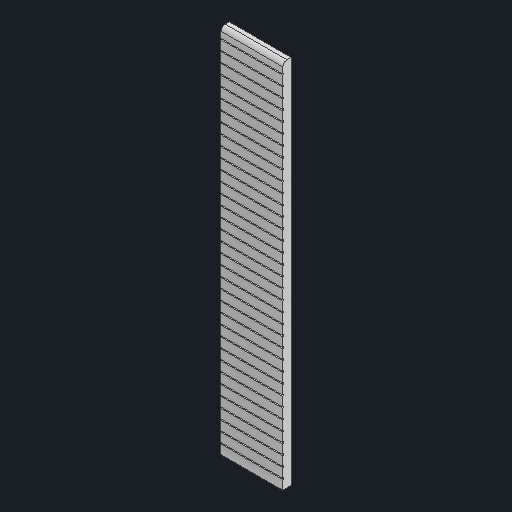
# Autodesk Inventor part: 7_1_2_1_vollet_cote_avant
Saved by Autodesk Inventor 2026 (Build 300175000, 175)
## iProperties
Created: 2025-06-21
Part Number: 7_1_2_1_vollet_cote_avant
Material: Generic
Document SubType Name: Modeling
Designer: remg9
Density: 1 g/cm^3
Appearance: Default
Author: remg9
Autodesk Inventor part; units mm, degrees
ref_plane "YZ Plane" through (0, 0, 0) normal (1, 0, 0) x (0, 1, 0)
ref_plane "XZ Plane" through (0, 0, 0) normal (0, 1, 0) x (-1, 0, 0)
ref_plane "XY Plane" through (0, 0, 0) normal (0, 0, 1) x (1, 0, 0)
sketch "Sketch1" plane through (0, 0, 0) normal (0, 0, 1) x (1, 0, 0)
  line L0 (0, 0) -> (30, 0)
  line L1 (30, 0) -> (30, 180)
  line L2 (30, 180) -> (0, 180)
  line L3 (0, 180) -> (0, 0)
  dimension "d0" = 180
  dimension "d1" = 30
  constraints: 8 end point, 2 parallel, 1 horizontal, 1 perpendicular
  measures "d0" distance of L0.end L1.end
  measures "d1" distance of L1.end L2.end
extrude "Extrusion1" add sketch "Sketch1" along normal blind 4
sketch "Sketch2" plane through (0, 0, 4) normal (0, 0, 1) x (1, 0, 0)
  line L0 (0, 175) -> (30, 175)
  line L1 (30, 175) -> (30, 174.5)
  line L2 (30, 174.5) -> (0, 174.5)
  line L3 (0, 174.5) -> (0, 175)
  line L4 (30, 0) -> (30, 180) projected
  line L5 (0, 180) -> (0, 0) projected
  line L6 (0, 170) -> (30, 170)
  line L7 (30, 170) -> (30, 169.5)
  line L8 (30, 169.5) -> (0, 169.5)
  line L9 (0, 169.5) -> (0, 170)
  line L10 (0, 165) -> (30, 165)
  line L11 (30, 165) -> (30, 164.5)
  line L12 (30, 164.5) -> (0, 164.5)
  line L13 (0, 164.5) -> (0, 165)
  line L14 (0, 160) -> (30, 160)
  line L15 (30, 160) -> (30, 159.5)
  line L16 (30, 159.5) -> (0, 159.5)
  line L17 (0, 159.5) -> (0, 160)
  line L18 (0, 155) -> (30, 155)
  line L19 (30, 155) -> (30, 154.5)
  line L20 (30, 154.5) -> (0, 154.5)
  line L21 (0, 154.5) -> (0, 155)
  line L22 (0, 150) -> (30, 150)
  line L23 (30, 150) -> (30, 149.5)
  line L24 (30, 149.5) -> (0, 149.5)
  line L25 (0, 149.5) -> (0, 150)
  line L26 (0, 145) -> (30, 145)
  line L27 (30, 145) -> (30, 144.5)
  line L28 (30, 144.5) -> (0, 144.5)
  line L29 (0, 144.5) -> (0, 145)
  line L30 (0, 140) -> (30, 140)
  line L31 (30, 140) -> (30, 139.5)
  line L32 (30, 139.5) -> (0, 139.5)
  line L33 (0, 139.5) -> (0, 140)
  line L34 (0, 135) -> (30, 135)
  line L35 (30, 135) -> (30, 134.5)
  line L36 (30, 134.5) -> (0, 134.5)
  line L37 (0, 134.5) -> (0, 135)
  line L38 (0, 130) -> (30, 130)
  line L39 (30, 130) -> (30, 129.5)
  line L40 (30, 129.5) -> (0, 129.5)
  line L41 (0, 129.5) -> (0, 130)
  line L42 (0, 125) -> (30, 125)
  line L43 (30, 125) -> (30, 124.5)
  line L44 (30, 124.5) -> (0, 124.5)
  line L45 (0, 124.5) -> (0, 125)
  line L46 (0, 120) -> (30, 120)
  line L47 (30, 120) -> (30, 119.5)
  line L48 (30, 119.5) -> (0, 119.5)
  line L49 (0, 119.5) -> (0, 120)
  line L50 (0, 115) -> (30, 115)
  line L51 (30, 115) -> (30, 114.5)
  line L52 (30, 114.5) -> (0, 114.5)
  line L53 (0, 114.5) -> (0, 115)
  line L54 (0, 110) -> (30, 110)
  line L55 (30, 110) -> (30, 109.5)
  line L56 (30, 109.5) -> (0, 109.5)
  line L57 (0, 109.5) -> (0, 110)
  line L58 (0, 105) -> (30, 105)
  line L59 (30, 105) -> (30, 104.5)
  line L60 (30, 104.5) -> (0, 104.5)
  line L61 (0, 104.5) -> (0, 105)
  line L62 (0, 100) -> (30, 100)
  line L63 (30, 100) -> (30, 99.5)
  line L64 (30, 99.5) -> (0, 99.5)
  line L65 (0, 99.5) -> (0, 100)
  line L66 (0, 95) -> (30, 95)
  line L67 (30, 95) -> (30, 94.5)
  line L68 (30, 94.5) -> (0, 94.5)
  line L69 (0, 94.5) -> (0, 95)
  line L70 (0, 90) -> (30, 90)
  line L71 (30, 90) -> (30, 89.5)
  line L72 (30, 89.5) -> (0, 89.5)
  line L73 (0, 89.5) -> (0, 90)
  line L74 (0, 85) -> (30, 85)
  line L75 (30, 85) -> (30, 84.5)
  line L76 (30, 84.5) -> (0, 84.5)
  line L77 (0, 84.5) -> (0, 85)
  line L78 (0, 80) -> (30, 80)
  line L79 (30, 80) -> (30, 79.5)
  line L80 (30, 79.5) -> (0, 79.5)
  line L81 (0, 79.5) -> (0, 80)
  line L82 (0, 75) -> (30, 75)
  line L83 (30, 75) -> (30, 74.5)
  line L84 (30, 74.5) -> (0, 74.5)
  line L85 (0, 74.5) -> (0, 75)
  line L86 (0, 70) -> (30, 70)
  line L87 (30, 70) -> (30, 69.5)
  line L88 (30, 69.5) -> (0, 69.5)
  line L89 (0, 69.5) -> (0, 70)
  line L90 (0, 65) -> (30, 65)
  line L91 (30, 65) -> (30, 64.5)
  line L92 (30, 64.5) -> (0, 64.5)
  line L93 (0, 64.5) -> (0, 65)
  line L94 (0, 60) -> (30, 60)
  line L95 (30, 60) -> (30, 59.5)
  line L96 (30, 59.5) -> (0, 59.5)
  line L97 (0, 59.5) -> (0, 60)
  line L98 (0, 55) -> (30, 55)
  line L99 (30, 55) -> (30, 54.5)
  line L100 (30, 54.5) -> (0, 54.5)
  line L101 (0, 54.5) -> (0, 55)
  line L102 (0, 50) -> (30, 50)
  line L103 (30, 50) -> (30, 49.5)
  line L104 (30, 49.5) -> (0, 49.5)
  line L105 (0, 49.5) -> (0, 50)
  line L106 (0, 45) -> (30, 45)
  line L107 (30, 45) -> (30, 44.5)
  line L108 (30, 44.5) -> (0, 44.5)
  line L109 (0, 44.5) -> (0, 45)
  line L110 (0, 40) -> (30, 40)
  line L111 (30, 40) -> (30, 39.5)
  line L112 (30, 39.5) -> (0, 39.5)
  line L113 (0, 39.5) -> (0, 40)
  line L114 (0, 35) -> (30, 35)
  line L115 (30, 35) -> (30, 34.5)
  line L116 (30, 34.5) -> (0, 34.5)
  line L117 (0, 34.5) -> (0, 35)
  line L118 (0, 30) -> (30, 30)
  line L119 (30, 30) -> (30, 29.5)
  line L120 (30, 29.5) -> (0, 29.5)
  line L121 (0, 29.5) -> (0, 30)
  line L122 (0, 25) -> (30, 25)
  line L123 (30, 25) -> (30, 24.5)
  line L124 (30, 24.5) -> (0, 24.5)
  line L125 (0, 24.5) -> (0, 25)
  line L126 (0, 20) -> (30, 20)
  line L127 (30, 20) -> (30, 19.5)
  line L128 (30, 19.5) -> (0, 19.5)
  line L129 (0, 19.5) -> (0, 20)
  line L130 (0, 15) -> (30, 15)
  line L131 (30, 15) -> (30, 14.5)
  line L132 (30, 14.5) -> (0, 14.5)
  line L133 (0, 14.5) -> (0, 15)
  line L134 (0, 10) -> (30, 10)
  line L135 (30, 10) -> (30, 9.5)
  line L136 (30, 9.5) -> (0, 9.5)
  line L137 (0, 9.5) -> (0, 10)
  line L138 (0, 5) -> (30, 5)
  line L139 (30, 5) -> (30, 4.5)
  line L140 (30, 4.5) -> (0, 4.5)
  line L141 (0, 4.5) -> (0, 5)
  line L142 (30, 180) -> (0, 180) projected
  point P0 (0, 4.5)
  point P1 (0, 9.5)
  point P2 (0, 14.5)
  point P3 (0, 19.5)
  point P4 (0, 24.5)
  point P5 (0, 29.5)
  point P6 (0, 34.5)
  point P7 (0, 39.5)
  point P8 (0, 44.5)
  point P9 (0, 49.5)
  point P10 (0, 54.5)
  point P11 (0, 59.5)
  point P12 (0, 64.5)
  point P13 (0, 69.5)
  point P14 (0, 74.5)
  point P15 (0, 79.5)
  point P16 (0, 84.5)
  point P17 (0, 89.5)
  point P18 (0, 94.5)
  point P19 (0, 99.5)
  point P20 (0, 104.5)
  point P21 (0, 109.5)
  point P22 (0, 114.5)
  point P23 (0, 119.5)
  point P24 (0, 124.5)
  point P25 (0, 129.5)
  point P26 (0, 134.5)
  point P27 (0, 139.5)
  point P28 (0, 144.5)
  point P29 (0, 149.5)
  point P30 (0, 154.5)
  point P31 (0, 159.5)
  point P32 (0, 164.5)
  point P33 (0, 169.5)
  dimension "d4" = 0.5
  dimension "d7" = 5
  dimension "d12" = 5
  constraints: 280 end point, 136 vertical alignment, 70 parallel, 68 collinear, 2 vertical, 1 horizontal, 1 perpendicular
  measures "d4" distance between parallel lines of L2 L0
  measures "d7" distance of L0.start L6.start
  measures "d12" distance between parallel lines of L142 L0
extrude "Extrusion2" cut sketch "Sketch2" against normal blind 0.5 contours L0 L1 L2 L3 | L6 L4 L8 L5 | L10 L4 L12 L5 | L14 L4 L16 L5 | L18 L4 L20 L5 | L22 L4 L24 L5 | L26 L4 L28 L5 | L30 L4 L32 L5 | L34 L4 L36 L5 | L38 L4 L40 L5 | L42 L4 L44 L5 | L46 L4 L48 L5 | L50 L4 L52 L5 | L54 L4 L56 L5 | L58 L4 L60 L5 | L62 L4 L64 L5 | L66 L4 L68 L5 | L70 L4 L72 L5 | L74 L4 L76 L5 | L78 L4 L80 L5 | L82 L4 L84 L5 | L86 L4 L88 L5 | L90 L4 L92 L5 | L94 L4 L96 L5 | L98 L4 L100 L5 | L102 L4 L104 L5 | L106 L4 L108 L5 | L110 L4 L112 L5 | L114 L4 L116 L5 | L118 L4 L120 L5 | L122 L4 L124 L5 | L126 L4 L128 L5 | L130 L4 L132 L5 | L134 L4 L136 L5 | L138 L4 L140 L5
fillet "Fillet1" radius 2 1 edges at (15, 180, 4)
body "Solid1"
